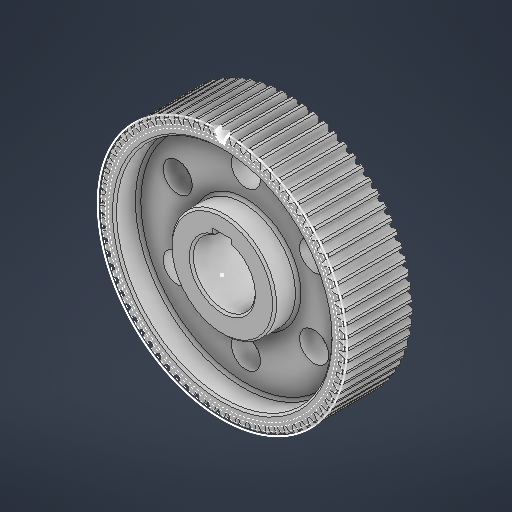
# Autodesk Inventor part: 低速大齿轮
Saved by Autodesk Inventor 2026 (Build 300175000, 175)
## iProperties
Created: 2026-08-27
Part Number: 低速大齿轮
Material: Generic
Document SubType Name: Modeling
Designer: 14170
Density: 1 g/cm^3
Appearance: Default
Author: 14170
Autodesk Inventor part; units mm, degrees
ref_plane "YZ Plane" through (0, 0, 0) normal (1, 0, 0) x (0, 1, 0)
ref_plane "XZ Plane" through (0, 0, 0) normal (0, 1, 0) x (-1, 0, 0)
ref_plane "XY Plane" through (0, 0, 0) normal (0, 0, 1) x (1, 0, 0)
sketch "Sketch1" plane through (0, 0, 0) normal (0, 0, 1) x (1, 0, 0)
  spline S0 degree 3 poles (-3.0418, 92.45) (-2.8054, 91.945) (-2.4509, 91.1874) (-2.0282, 90.1554) (-1.7309, 89.3738) (-1.4545, 88.5842) (-1.2721, 87.9843) (-1.1514, 87.5837) (-1.0645, 87.3928) (-0.9465, 87.2189) (-0.7951, 87.0728) (-0.6167, 86.9615) (-0.4183, 86.8902) (-0.2088, 86.8705) (0, 86.8773) (0.2088, 86.8705) (0.4183, 86.8902) (0.6167, 86.9615) (0.7951, 87.0728) (0.9465, 87.2189) (1.0645, 87.3928) (1.1514, 87.5837) (1.2721, 87.9843) (1.4545, 88.5842) (1.7309, 89.3738) (2.0282, 90.1554) (2.4509, 91.1874) (2.8054, 91.945) (3.0418, 92.45) knots 0 0 0 0 0.167239 0.250865 0.33449 0.418114 0.501737 0.522641 0.543532 0.56442 0.58531 0.606178 0.627064 0.647936 0.668842 0.689749 0.710621 0.731506 0.752375 0.773264 0.794152 0.815043 0.835947 0.91957 1.003195 1.08682 1.170445 1.337685 1.337685 1.337685 1.337685
  circle A0 centre (0, 0) radius 86.875 construction
  circle A1 centre (0, 0) radius 84.5723 construction
  circle A2 centre (0, 0) radius 90 construction
  circle A3 centre (0, 0) radius 92.5
  point P0 (-2.3494, 90.9276)
  point P1 (-2.0315, 90.1542)
  point P2 (-1.7344, 89.3725)
  point P3 (-1.46, 88.5825)
  point P4 (-1.2118, 87.784)
  point P5 (-1.1469, 87.5852)
  point P6 (-1.0593, 87.3956)
  point P7 (-0.9409, 87.2235)
  point P8 (-0.7905, 87.0785)
  point P9 (-0.6134, 86.9682)
  point P10 (-0.4164, 86.8988)
  point P11 (-0.2091, 86.8749)
  point P12 (0, 86.875)
  point P13 (0.2091, 86.8749)
  point P14 (0.4164, 86.8988)
  point P15 (0.6134, 86.9682)
  point P16 (0.7905, 87.0785)
  point P17 (0.9409, 87.2235)
  point P18 (1.0593, 87.3956)
  point P19 (1.1469, 87.5852)
  point P20 (1.2118, 87.784)
  point P21 (1.46, 88.5825)
  point P22 (1.7344, 89.3725)
  point P23 (2.0315, 90.1542)
  point P24 (2.3494, 90.9276)
  constraints: 4 centre point, 2 point on circle, 59 other
extrude "拉伸1" add sketch "Sketch1" against normal blind 50
chamfer "倒角1" distance 1.5 angle 45 2 edges at (-3.0418, -92.45, 0) (-3.0418, -92.45, -50)
extrude "拉伸2" cut sketch "Sketch1" against normal through all contours A3 S0 picked at (-0.1422, 90.2637)
pattern_circular "环形阵列1" count 73 over 360 about axis through (0, 0, -0.75) along (0, 0, 1) of "拉伸2"
sketch "草图2" plane through (0, 0, 0) normal (0, 0, 1) x (1, 0, 0)
  arc A0 (-7, 21.9089) -> (7, 21.9089) centre (0, 0) ccw
  line L0 (0, 26.8) -> (7, 26.8)
  line L1 (7, 26.8) -> (7, 21.9089)
  line L2 (0, 26.8) -> (-7, 26.8)
  line L3 (-7, 26.8) -> (-7, 21.9089)
  dimension "d10" = 46
  dimension "d11" = 7
  dimension "d12" = 7
  constraints: 8 end point, 2 perpendicular, 2 point on circle, 1 centre point, 1 coincident, 1 horizontal, 1 point on line
  measures "d10" diameter of A0
  measures "d11" distance of L0.start L0.end
  measures "d12" distance of L0.start L2.end
extrude "拉伸3" cut sketch "草图2" against normal through all
chamfer "倒角2" distance 1.5 angle 45 2 edges at (0, -23, 0) (0, -23, -50)
sketch "草图3" plane through (0, 0, 0) normal (0, 0, 1) x (1, 0, 0)
  circle A0 centre (0, 0) radius 38.8
  circle A1 centre (0, 0) radius 80
  dimension "d18" = 77.6
  dimension "d19" = 160
  constraints: 2 centre point, 2 coincident
  measures "d18" diameter of A0
  measures "d19" diameter of A1
extrude "拉伸4" cut sketch "草图3" against normal blind 17.5
chamfer "倒角3" distance 1.5 angle 45 2 edges at (-80, 0, 0) (-38.8, 0, 0)
fillet "圆角1" radius 2 2 edges at (-80, 0, -17.5) (-38.8, 0, -17.5)
sketch "草图4" plane through (0, 0, -17.5) normal (0, 0, 1) x (1, 0, 0)
  circle A0 centre (0, 0) radius 58.45
  circle A1 centre (0, 58.45) radius 10.85
  circle A2 centre (-50.6192, 29.225) radius 10.85
  circle A3 centre (-50.6192, -29.225) radius 10.85
  circle A4 centre (0, -58.45) radius 10.85
  circle A5 centre (50.6192, -29.225) radius 10.85
  circle A6 centre (50.6192, 29.225) radius 10.85
  dimension "d26" = 116.9
  dimension "d27" = 21.7
  dimension "d30" = 360
  constraints: 6 centre point, 1 coincident, 1 vertical alignment, 15 other
  measures "d27" diameter of A1
extrude "拉伸5" cut sketch "草图4" against normal through all contours A6 A0 | A0 A6 | A5 A0 | A0 A5 | A1 A0 | A0 A1 | A4 A0 | A0 A4 | A2 A0 | A0 A2 | A3 A0 | A0 A3
sketch "草图5" plane through (0, 0, -50) normal (0, 0, -1) x (-1, 0, 0)
  circle A0 centre (0, 0) radius 38.8
  circle A1 centre (0, 0) radius 78
  constraints: 2 centre point, 2 coincident
extrude "拉伸6" cut sketch "草图5" against normal blind 17.5
fillet "圆角2" radius 2 2 edges at (78, 0, -32.5) (38.8, 0, -32.5)
chamfer "倒角4" distance 1.5 angle 45 2 edges at (78, 0, -50) (38.8, 0, -50)
equation "\"d0\" = 面宽"
equation "\"模数\" = 2.5"
equation "\"压力角\" = 20deg"
equation "\"单位截面轮廓间隙\" = 0.25"
equation "\"单位圆半径\" = 0.35"
equation "\"头直径\" = 185"
equation "\"齿根圆直径\" = 173.75"
equation "\"基底直径\" = 169.14467"
equation "\"面宽\" = 50"
equation "\"螺旋角\" = 0"
equation "\"变位系数\" = 0"
equation "\"单位齿顶高修改\" = 0"
equation "\"周节\" = 7.853982"
equation "\"单位侧隙位移\" = 0"
equation "\"总工具位移\" = 0"
equation "\"内啮合\" = 0"
